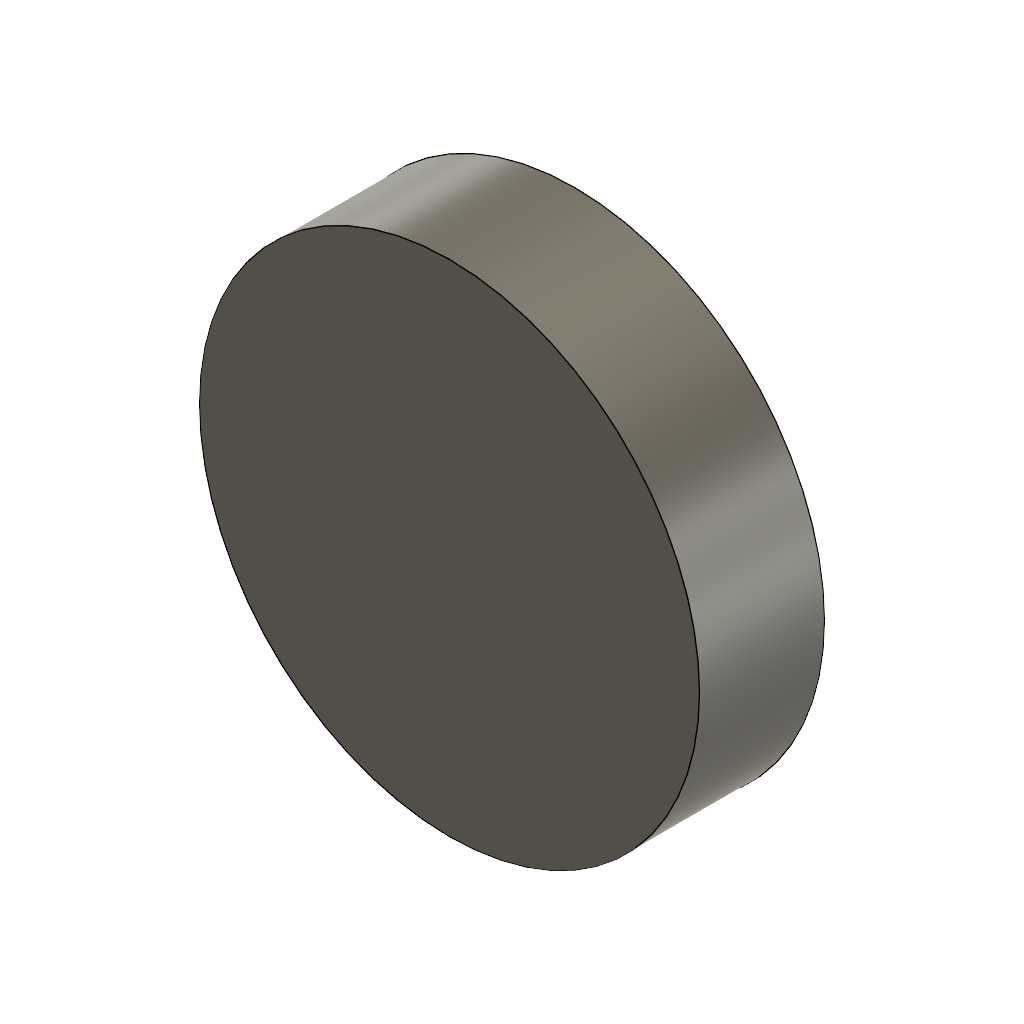
regions_full_circle (Autodesk Fusion 360 design; units mm, degrees)
part number: 2026-11-10-15-06-45-265
Autodesk Fusion 360 part; units mm, degrees
sketch "Sketch1" plane through (0, 0, 0) normal (0, 0, 1) x (1, 0, 0)
  line L0 (-5, -3) -> (5, -3)
  line L1 (5, -3) -> (5, 3)
  line L2 (5, 3) -> (-5, 3)
  line L3 (-5, 3) -> (-5, -3)
  circle A0 centre (0, 0) radius 4
extrude "Extrude1" add sketch "Sketch1" along normal blind 2 contours L0 L2 A0 | L0 A0 | L2 A0
